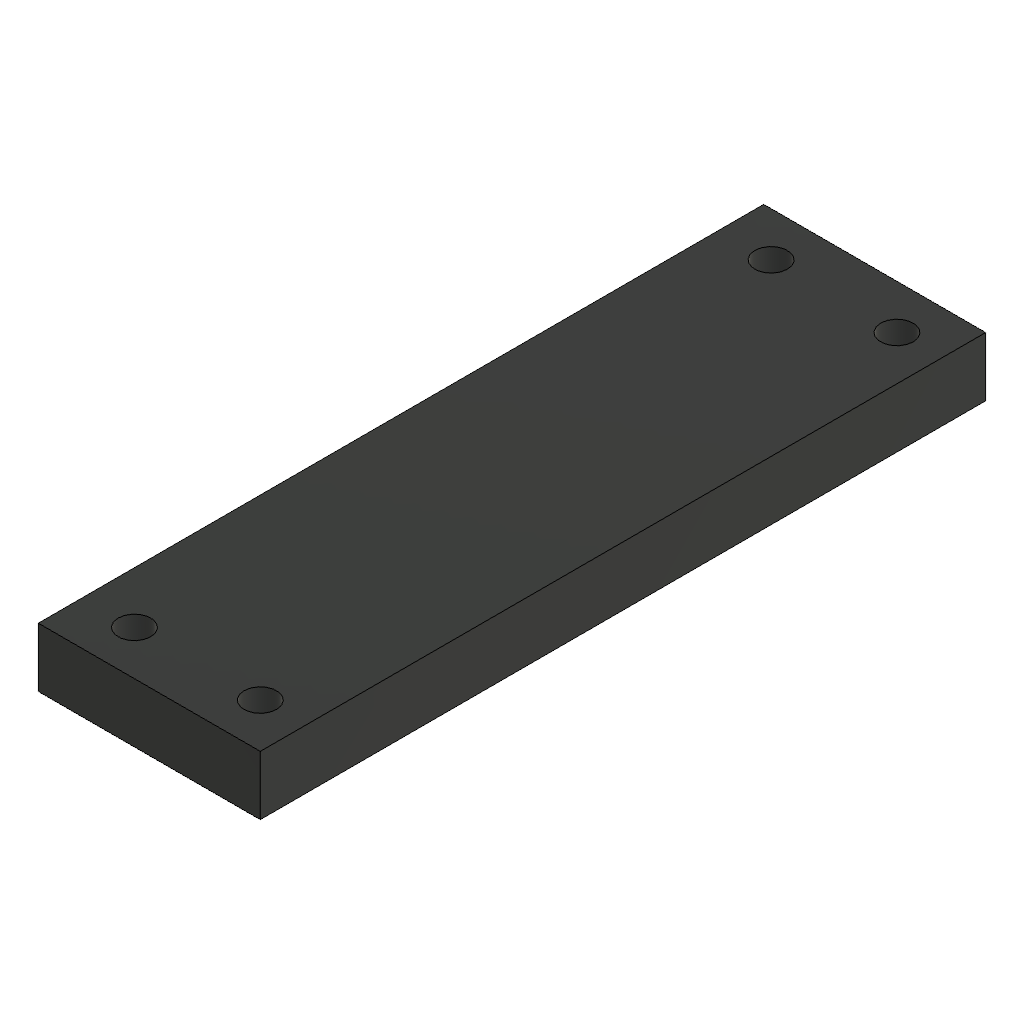
root_cap (Autodesk Fusion 360 design; units mm, degrees)
part number: 2026-10-10-17-06-19-704
Autodesk Fusion 360 part; units mm, degrees
sketch "Upper root jaw sketch" plane through (0, 0, 0) normal (0, 0, 1) x (1, 0, 0)
  line L0 (-4, -49) -> (26, -49)
  line L1 (26, -49) -> (26, 49)
  line L2 (26, 49) -> (-4, 49)
  line L3 (-4, 49) -> (-4, -49)
extrude "Upper root jaw" add sketch "Upper root jaw sketch" along normal blind 8
ref_plane "WorkPlane1" through (0, 0, -0.05) normal (0, 0, 1) x (1, 0, 0)
sketch "Cap bolt 3 -43 sketch" plane through (0, 0, -0.05) normal (0, 0, 1) x (1, 0, 0)
  circle A0 centre (3, -43) radius 2.2
  dimension "d430" = 4.4
  measures "d430" diameter of A0
extrude "Cap bolt 3 -43" cut sketch "Cap bolt 3 -43 sketch" along normal blind 8.1
ref_plane "WorkPlane2" through (0, 0, -0.05) normal (0, 0, 1) x (1, 0, 0)
sketch "Cap bolt 3 43 sketch" plane through (0, 0, -0.05) normal (0, 0, 1) x (1, 0, 0)
  circle A0 centre (3, 43) radius 2.2
  dimension "d435" = 4.4
  measures "d435" diameter of A0
extrude "Cap bolt 3 43" cut sketch "Cap bolt 3 43 sketch" along normal blind 8.1
ref_plane "WorkPlane3" through (0, 0, -0.05) normal (0, 0, 1) x (1, 0, 0)
sketch "Cap bolt 20 -43 sketch" plane through (0, 0, -0.05) normal (0, 0, 1) x (1, 0, 0)
  circle A0 centre (20, -43) radius 2.2
  dimension "d440" = 4.4
  measures "d440" diameter of A0
extrude "Cap bolt 20 -43" cut sketch "Cap bolt 20 -43 sketch" along normal blind 8.1
ref_plane "WorkPlane4" through (0, 0, -0.05) normal (0, 0, 1) x (1, 0, 0)
sketch "Cap bolt 20 43 sketch" plane through (0, 0, -0.05) normal (0, 0, 1) x (1, 0, 0)
  circle A0 centre (20, 43) radius 2.2
  dimension "d445" = 4.4
  measures "d445" diameter of A0
extrude "Cap bolt 20 43" cut sketch "Cap bolt 20 43 sketch" along normal blind 8.1
equation "d430 = m4Clearance"
equation "d435 = m4Clearance"
equation "d440 = m4Clearance"
equation "d445 = m4Clearance"
equation "m4Clearance = 4.4 mm" comment "Root clamp bolt holes"
named bodies: "root_cap - printable solid"
